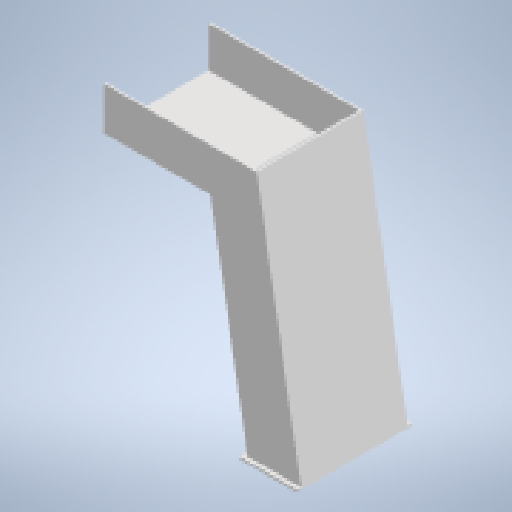
# Autodesk Inventor part: RDS-7001
Saved by Autodesk Inventor 2026 (Build 300175000, 175)
## iProperties
Created: 2026-10-26
Part Number: RDS-7001
Material: Типовые
Document SubType Name: Modeling
Designer: user
Density: 1 g/cm^3
Appearance: По умолчанию
Author: user
Autodesk Inventor part; units mm, degrees
ref_plane "YZ Plane" through (0, 0, 0) normal (1, 0, 0) x (0, 1, 0)
ref_plane "XZ Plane" through (0, 0, 0) normal (0, 1, 0) x (-1, 0, 0)
ref_plane "XY Plane" through (0, 0, 0) normal (0, 0, 1) x (1, 0, 0)
sketch "Эскиз1" plane through (0, 0, 0) normal (0, 0, 1) x (1, 0, 0)
  line L0 (0, 0) -> (250, 0)
  line L1 (0, 0) -> (-173.6482, 984.8078)
  line L2 (250, 0) -> (41.0864, 1184.8078)
  line L3 (-173.6482, 984.8078) -> (-673.6482, 984.8078)
  line L4 (-673.6482, 984.8078) -> (-673.6482, 1184.8078)
  line L5 (-673.6482, 1184.8078) -> (41.0864, 1184.8078)
  dimension "d0" = 250
  dimension "d1" = 1000
  dimension "d2" = 100
  dimension "d4" = 500
  dimension "d5" = 200
  constraints: 12 end point, 2 horizontal, 2 perpendicular, 1 parallel
  measures "d0" distance of L0.start L0.end
  measures "d1" distance of L0.start L1.end
  measures "d2" angle of L0 L1
  measures "d4" distance of L1.end L3.end
  measures "d5" distance of L3.end L4.end
extrude "Выдавливание1" add sketch "Эскиз1" against normal blind 500
shell "Оболочка3" thickness 10 removed faces 3 at (-673.6482, 1118.1411, -166.6667) at (-197.1584, 1184.8078, -166.6667) at (83.3333, 0, -166.6667)
sketch "Эскиз2" plane through (0, 0, 0) normal (0, -1, 0) x (1, 0, 0)
  line L0 (-15, 20) -> (250, 20)
  line L1 (250, 20) -> (250, -520)
  line L2 (250, -520) -> (-15, -520)
  line L3 (-20, -515) -> (-20, 15)
  line L4 (-20, 20) -> (250, -520) construction
  line L5 (250, 20) -> (-20, -520) construction
  line L6 (0, 0) -> (250, 0) projected
  line L7 (0, 0) -> (0, -500) projected
  line L8 (250, -500) -> (0, -500) projected
  arc A0 (-15, 20) -> (-20, 15) centre (-15, 15) ccw
  arc A1 (-20, -515) -> (-15, -520) centre (-15, -515) ccw
  point P0 (115, -250)
  dimension "d11" = 270
  dimension "d12" = 540
  dimension "d13" = 20
  dimension "d14" = 20
  dimension "d15" = 5
  constraints: 12 end point, 4 point on circle, 4 point on line, 4 tangent, 2 centre point, 2 midpoint, 2 parallel, 1 equal radius, 1 horizontal, 1 perpendicular
  measures "d11" distance of L4.start L0.end
  measures "d12" distance of L0.end L1.end
  measures "d13" horizontal distance of L6.start L4.start
  measures "d14" horizontal distance of L6.start L4.start
  measures "d15" radius of A0
extrude "Выдавливание2" add sketch "Эскиз2" against normal blind 10 contours L0 L1 L6 L7 L8 L2 A1 L3 A0
